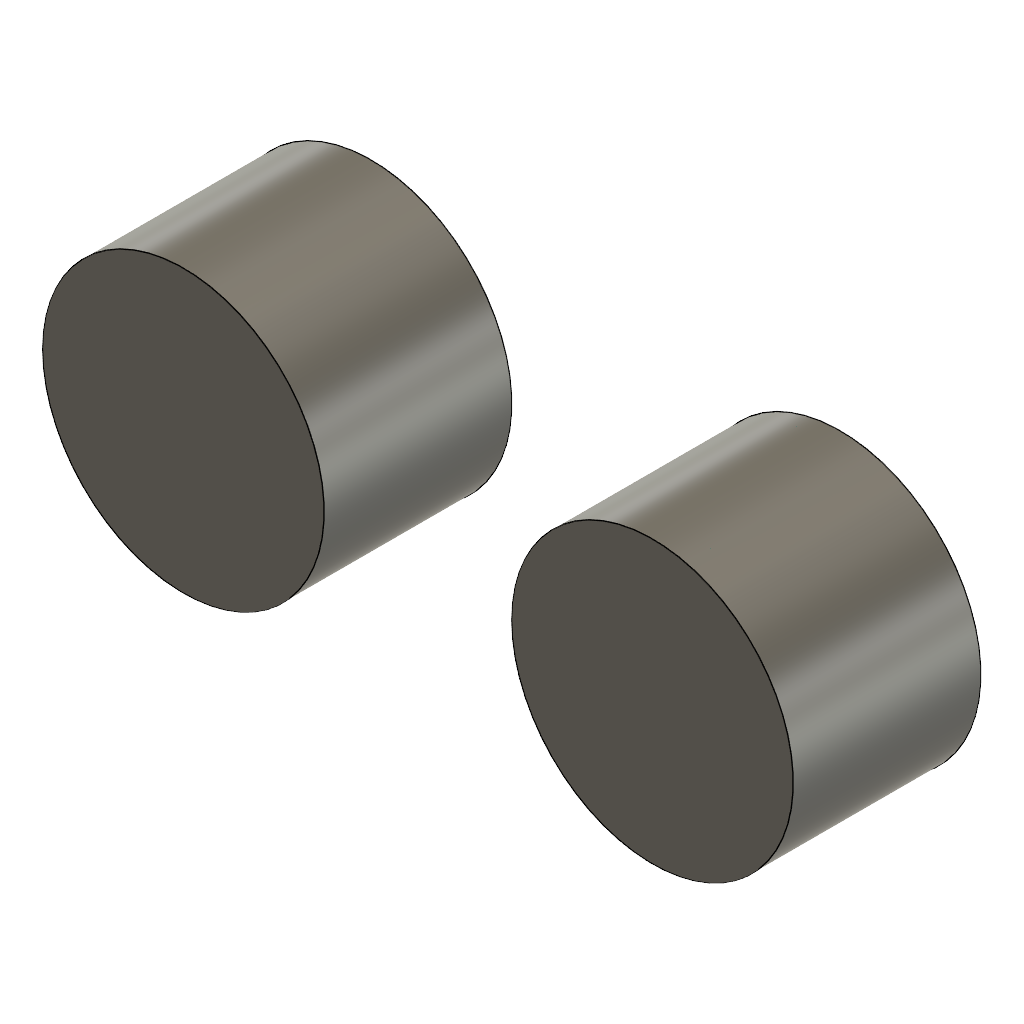
disjoint_new_body (Autodesk Fusion 360 design; units mm, degrees)
part number: 2026-11-10-15-06-49-799
Autodesk Fusion 360 part; units mm, degrees
sketch "Sketch1" plane through (0, 0, 0) normal (0, 0, 1) x (1, 0, 0)
  circle A0 centre (0, 0) radius 3
  circle A1 centre (10, 0) radius 3
extrude "Extrude1" add sketch "Sketch1" along normal blind 4 makes body 1 at (2.9963, -0.1495, 2.6667) makes body 2 at (12.9963, -0.1495, 2.6667)
